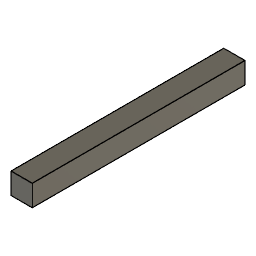
region_B (Autodesk Fusion 360 design; units mm, degrees)
Autodesk Fusion 360 part; units mm, degrees
sketch "Sketch1" plane through (0, 0, 0) normal (0, 0, 1) x (1, 0, 0)
  line L0 (-10, -10) -> (-8, -10)
  line L1 (-8, -10) -> (-8, 10)
  line L2 (-8, 10) -> (-10, 10)
  line L3 (-10, 10) -> (-10, -10)
  line L4 (-1, -10) -> (1, -10)
  line L5 (1, -10) -> (1, 10)
  line L6 (1, 10) -> (-1, 10)
  line L7 (-1, 10) -> (-1, -10)
  line L8 (8, -10) -> (10, -10)
  line L9 (10, -10) -> (10, 10)
  line L10 (10, 10) -> (8, 10)
  line L11 (8, 10) -> (8, -10)
  line L12 (-15, 0) -> (15, 0)
extrude "Extrude1" add sketch "Sketch1" along normal blind 2 contours L4 L5 L7 L12 | L5 L6 L7 L12
